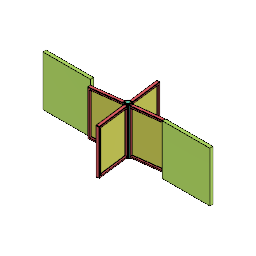
Revolving Door v0 (Autodesk Fusion 360 design; units mm, degrees)
Autodesk Fusion 360 part; units mm, degrees
sketch "Sketch1" plane through (0, 0, 0) normal (0, 0, 1) x (1, 0, 0) in component "base"
  line L0 (500, -10) -> (-500, -10)
  line L1 (-500, -10) -> (-500, 10)
  line L2 (-500, 10) -> (500, 10)
  line L3 (500, 10) -> (500, -10)
  line L4 (210, 10) -> (-210, 10)
  line L5 (-210, 10) -> (-210, -10)
  line L6 (-210, -10) -> (210, -10)
  line L7 (210, -10) -> (210, 10)
  line L8 (0, -10) -> (0, 10)
  line L9 (-215, 10) -> (-215, -10)
  line L10 (215, 10) -> (215, -10)
  dimension "d1" = 1000
  dimension "d2" = 20
  dimension "d3" = 420
  constraint horizontal L0
  constraint perpendicular L0 L1
  constraint parallel L0 L2
  constraint parallel L1 L3
  constraint horizontal L4
  constraint perpendicular L4 L5
  constraint parallel L4 L6
  constraint parallel L5 L7
  constraint midpoint L0 L8.start
  constraint midpoint L4 L8.end
  constraint perpendicular L4 L8
  constraint coincident L2 L9.start
  constraint coincident L0 L9.end
  constraint perpendicular L0 L9
  constraint coincident L2 L10.start
  constraint coincident L0 L10.end
  constraint perpendicular L0 L10
  measures "d1" distance of L1.end L2.end
  measures "d2" distance of L0.end L1.end
  measures "d3" distance of L5.end L6.end
sketch "Sketch1 (2)" plane through (0, 0, 0) normal (0, 1, 0) x (1, 0, 0) in component "glass door"
  line L0 (0, 0) -> (200, 0)
  line L1 (200, 0) -> (200, -270)
  line L2 (200, -270) -> (0, -270)
  line L3 (0, -270) -> (0, 0)
  line L4 (15, -15) -> (185, -15)
  line L5 (185, -15) -> (185, -255)
  line L6 (185, -255) -> (15, -255)
  line L7 (15, -255) -> (15, -15)
  dimension "d4" = 200
  dimension "d5" = 270
  dimension "d6" = 15
  constraint horizontal L0
  constraint vertical L1
  constraint horizontal L2
  constraint vertical L3
  constraint coincident L0.start L3.end
  measures "d4" distance of L0.start L0.end
  measures "d5" distance of L0.start L2.end
extrude "Extrude1" add sketch "Sketch1 (2)" along normal mid plane 20 makes body 1 in component "glass door"
move_body "Move1" bodies 1 to x (1, 0, 0) y (0, 1, 0) z (0, 0, 1) at (10, 0, 0) in component "glass door"
sketch "Sketch2" plane through (0, 0, 270) normal (0, 0, 1) x (-1, 0, 0) in component "glass door"
  line L0 (-210, 10) -> (-210, -10)
  line L1 (-210, -10) -> (-10, -10)
  line L2 (-10, -10) -> (-10, 10)
  line L3 (-10, 10) -> (-210, 10)
  line L4 (-10, 10) -> (-20, 10)
  line L5 (-20, 10) -> (-20, -10)
  line L6 (-10, -10) -> (-20, -10)
  line L7 (-10, -10) -> (-10, 10)
  line L8 (-15, -6.5) -> (-15, 6.5)
  line L9 (-15, -6.5) -> (-15, -5)
  line L10 (-20, -5) -> (-15, -5)
  line L11 (-20, 10) -> (-20, 5)
  line L12 (-15, 5) -> (-20, 5)
  line L13 (-20, -10) -> (-20, -7.5)
  line L14 (-14, -7.5) -> (-10, -7.5)
  line L15 (-10, 10) -> (-10, 7.5)
  line L16 (-10, 7.5) -> (-14, 7.5)
  arc A0 (-15, -6.5) -> (-14, -7.5) centre (-14, -6.5) ccw
  arc A1 (-14, 7.5) -> (-15, 6.5) centre (-14, 6.5) ccw
  dimension "d9" = 10
  dimension "d10" = 2.5
  dimension "d11" = 2.5
  dimension "d12" = 1
  dimension "d13" = 1
  constraint coincident L2.end L3.start
  constraint perpendicular L2 L4
  constraint coincident L1 L5.end
  constraint perpendicular L1 L5
  constraint coincident L1.end L2.start
  constraint perpendicular L1 L8
  constraint coincident L8 L9.end
  constraint perpendicular L1 L9
  constraint coincident L5 L10.start
  constraint perpendicular L8 L10
  constraint coincident L5 L11.end
  constraint perpendicular L3 L11
  constraint coincident L8 L12.start
  constraint perpendicular L8 L12
  constraint perpendicular L1 L13
  constraint coincident L2 L14.end
  constraint perpendicular L2 L14
  constraint perpendicular L4 L15
  constraint coincident L13.end L14
  constraint tangent L14 A0
  constraint tangent L9 A0
  constraint tangent L16 A1
  constraint tangent L8 A1
  measures "d9" distance of L2.end L4.end
  measures "d10" distance of L5.end L13.end
  measures "d11" distance of L2.end L15.end
  measures "d12" radius of A0
  measures "d13" radius of A1
extrude "Extrude2" cut sketch "Sketch2" against normal blind 300 contours L2 L3 L4 L5 L7 L8 L11 L12 L15 L16 A1 | L1 L2 L5 L6 L7 L8 L9 L10 L13 L14 A0 bodies 1 in component "glass door"
sketch "Sketch1 (3)" plane through (0, 0, 0) normal (0, 0, 1) x (1, 0, 0) in component "revolver base"
  circle A0 centre (0, 0) radius 10
  circle A1 centre (0, 0) radius 15
  dimension "d16" = 20
  dimension "d17" = 30
  constraint coincident A0.centre A1.centre
  measures "d16" diameter of A0
  measures "d17" diameter of A1
move_body "Move2" bodies 1 to x (1, 0, 0) y (0, 1, 0) z (0, 0, 1) at (0, 0, 5) in component "glass door"
extrude "Extrude1'" add sketch "Sketch1 (3)" along normal blind 5 separate body makes body 2 in component "revolver base"
sketch "Sketch1 (4)" plane through (0, 0, 5) normal (0, 0, 1) x (-1, 0, 0) in component "revolver"
  circle A0 centre (0, 0) radius 10
  circle A1 centre (0, 0) radius 15
  circle A2 centre (0, 0) radius 10
  line L0 (0, -10) -> (-20, -10)
  line L1 (-20, 10) -> (0, 10)
  line L2 (-10, -7.4988) -> (-14, -7.4988)
  line L3 (-15, -6.4988) -> (-15, 6.5)
  line L4 (-14, 7.5) -> (-10, 7.5)
  arc A3 (-15, -6.4988) -> (-14, -7.4988) centre (-14, -6.4988) ccw
  arc A4 (-14, 7.5) -> (-15, 6.5) centre (-14, 6.5) ccw
  line L5 (-15, -5) -> (-20, -5)
  line L6 (-15, 5) -> (-20, 5)
  line L7 (-20, -10) -> (-20, -5)
  line L8 (-20, 5) -> (-20, 10)
  line L9 (10, 0) -> (10, -20)
  line L10 (7.4988, -10) -> (7.4988, -14)
  arc A5 (6.4988, -15) -> (7.4988, -14) centre (6.4988, -14) ccw
  line L11 (6.4988, -15) -> (-6.5, -15)
  line L12 (5, -15) -> (5, -20)
  line L13 (10, -20) -> (5, -20)
  line L14 (-5, -15) -> (-5, -20)
  line L15 (-5, -20) -> (-10, -20)
  line L16 (-10, -20) -> (-10, 0)
  line L17 (-7.5, -14) -> (-7.5, -10)
  arc A6 (-7.5, -14) -> (-6.5, -15) centre (-6.5, -14) ccw
  line L18 (0, 10) -> (20, 10)
  line L19 (10, 7.4988) -> (14, 7.4988)
  arc A7 (15, 6.4988) -> (14, 7.4988) centre (14, 6.4988) ccw
  line L20 (15, 6.4988) -> (15, -6.5)
  line L21 (15, 5) -> (20, 5)
  line L22 (20, 10) -> (20, 5)
  line L23 (15, -5) -> (20, -5)
  line L24 (20, -5) -> (20, -10)
  line L25 (20, -10) -> (0, -10)
  line L26 (14, -7.5) -> (10, -7.5)
  arc A8 (14, -7.5) -> (15, -6.5) centre (14, -6.5) ccw
  line L27 (-10, 0) -> (-10, 20)
  line L28 (-7.4988, 10) -> (-7.4988, 14)
  arc A9 (-6.4988, 15) -> (-7.4988, 14) centre (-6.4988, 14) ccw
  line L29 (-6.4988, 15) -> (6.5, 15)
  line L30 (-5, 15) -> (-5, 20)
  line L31 (-10, 20) -> (-5, 20)
  line L32 (5, 15) -> (5, 20)
  line L33 (5, 20) -> (10, 20)
  line L34 (10, 20) -> (10, 0)
  line L35 (7.5, 14) -> (7.5, 10)
  arc A10 (7.5, 14) -> (6.5, 15) centre (6.5, 14) ccw
  dimension "d20" = 20
  dimension "d21" = 1
  dimension "d23" = 360
  constraint coincident A0.centre A1.centre
  constraint horizontal L0
  constraint vertical L7
  constraint horizontal L1
  constraint coincident A2 L0.start
  constraint parallel L0 L2
  constraint perpendicular L2 L3
  constraint perpendicular L3 L4
  constraint tangent L2 A3
  constraint tangent L3 A3
  constraint tangent L3 A4
  constraint tangent L4 A4
  constraint equal A3 A4
  constraint coincident L3 L5.start
  constraint perpendicular L3 L5
  constraint coincident L3 L6.start
  constraint coincident L6.end L7
  constraint perpendicular L6 L7
  constraint collinear L7 L8
  measures "d20" diameter of A2
  measures "d21" radius of A3
extrude "Extrude3" add sketch "Sketch1 (4)" along normal blind 275 separate body contours A0 A2 | A0 A2 L9 L25 | A0 A2 L18 L34 | A0 A2 L1 L27 | A0 A2 L0 L16 | A1 L9 L25 L26 | A1 L18 L19 L34 | A1 L1 L27 L28 | A1 L18 L34 L35 | A1 L0 L16 L17 | A1 L9 L10 L25 | A1 L20 L23 L24 L25 L26 A8 | A1 L18 L19 A7 L20 L21 L22 | A1 L0 L2 L16 | A1 L1 L4 L27 | A1 L27 L28 A9 L29 L30 L31 | A1 L29 L32 L33 L34 L35 A10 | A1 L11 L14 L15 L16 L17 A6 | A1 L9 L10 A5 L11 L12 L13 | A1 L0 L2 L3 A3 L5 L7 | A1 L1 L3 L4 A4 L6 L8 makes body 3 in component "revolver"
move_body "Move3" bodies 1 to x (1, 0, 0) y (0, 1, 0) z (0, 0, 1) at (150, 0, 0) in component "glass door"
copy_body "CopyPasteBodies1" bodies 1 makes body 4 in component "glass door"
move_body "Move4" bodies 4 to x (1, 0, 0) y (0, 1, 0) z (0, 0, 1) at (-250, 0, 0) in component "glass door"
move_body "Move5" bodies 4 to x (-1, 0, 0) y (0, -1, 0) z (0, 0, 1) at (50, 0, 0) in component "glass door"
copy_body "CopyPasteBodies2" bodies 4 makes body 5 in component "glass door"
move_body "Move6" bodies 5 to x (0, 1, 0) y (-1, 0, 0) z (0, 0, 1) at (150, -150, 0) in component "glass door"
copy_body "CopyPasteBodies3" bodies 5 makes body 6 in component "glass door"
move_body "Move7" bodies 6 to x (-1, 0, 0) y (0, -1, 0) z (0, 0, 1) at (300, 0, 0) in component "glass door"
extrude "Extrude4" add sketch "Sketch1 (4)" against normal blind 5 contours A0 A2 bodies 3 in component "revolver"
extrude "Extrude1''" add sketch "Sketch1" along normal blind 300 separate body contours L0 L2 L3 L10 | L0 L1 L2 L9 makes body 7 at (-310, -10, 100) makes body 8 at (405, -10, 100) in component "base"
sketch "Sketch2 (2)" plane through (0, 0, 280) normal (0, 0, 1) x (-1, 0, 0) in component "revolver"
  line L0 (-7.4988, 10) -> (-7.4988, 14)
  arc A0 (-6.4988, 15) -> (-7.4988, 14) centre (-6.4988, 14) ccw
  line L1 (-6.4988, 15) -> (-5, 15)
  line L2 (-5, 15) -> (-5, 20)
  line L3 (-5, 20) -> (-10, 20)
  line L4 (-10, 20) -> (-10, 10)
  line L5 (-10, 10) -> (-20, 10)
  line L6 (-20, 10) -> (-20, 5)
  line L7 (-20, 5) -> (-15, 5)
  line L8 (-15, 5) -> (-15, 6.5)
  arc A1 (-14, 7.5) -> (-15, 6.5) centre (-14, 6.5) ccw
  line L9 (-14, 7.5) -> (-10, 7.5)
  line L10 (-10, 7.5) -> (-10, -7.4988)
  line L11 (-10, -7.4988) -> (-14, -7.4988)
  arc A2 (-15, -6.4988) -> (-14, -7.4988) centre (-14, -6.4988) ccw
  line L12 (-15, -6.4988) -> (-15, -5)
  line L13 (-15, -5) -> (-20, -5)
  line L14 (-20, -5) -> (-20, -10)
  line L15 (-20, -10) -> (-10, -10)
  line L16 (-10, -10) -> (-10, -20)
  line L17 (-10, -20) -> (-5, -20)
  line L18 (-5, -20) -> (-5, -15)
  line L19 (-5, -15) -> (-6.5, -15)
  arc A3 (-7.5, -14) -> (-6.5, -15) centre (-6.5, -14) ccw
  line L20 (-7.5, -14) -> (-7.5, -10)
  line L21 (-7.5, -10) -> (7.4988, -10)
  line L22 (7.4988, -10) -> (7.4988, -14)
  arc A4 (6.4988, -15) -> (7.4988, -14) centre (6.4988, -14) ccw
  line L23 (6.4988, -15) -> (5, -15)
  line L24 (5, -15) -> (5, -20)
  line L25 (5, -20) -> (10, -20)
  line L26 (10, -20) -> (10, -10)
  line L27 (10, -10) -> (20, -10)
  line L28 (20, -10) -> (20, -5)
  line L29 (20, -5) -> (15, -5)
  line L30 (15, -5) -> (15, -6.5)
  arc A5 (14, -7.5) -> (15, -6.5) centre (14, -6.5) ccw
  line L31 (14, -7.5) -> (10, -7.5)
  line L32 (10, -7.5) -> (10, 7.4988)
  line L33 (10, 7.4988) -> (14, 7.4988)
  arc A6 (15, 6.4988) -> (14, 7.4988) centre (14, 6.4988) ccw
  line L34 (15, 6.4988) -> (15, 5)
  line L35 (15, 5) -> (20, 5)
  line L36 (20, 5) -> (20, 10)
  line L37 (20, 10) -> (10, 10)
  line L38 (10, 10) -> (10, 20)
  line L39 (10, 20) -> (5, 20)
  line L40 (5, 20) -> (5, 15)
  line L41 (5, 15) -> (6.5, 15)
  arc A7 (7.5, 14) -> (6.5, 15) centre (6.5, 14) ccw
  line L42 (7.5, 14) -> (7.5, 10)
  line L43 (7.5, 10) -> (-7.4988, 10)
  circle A8 centre (0, 0) radius 10
  dimension "d55" = 20
  constraint coincident A8.centre origin
  measures "d55" diameter of A8
extrude "Extrude5" add sketch "Sketch2 (2)" along normal blind 5 contours A8 bodies 3 in component "revolver"
sketch "Sketch2 (3)" plane through (0, 0, 280) normal (0, 0, 1) x (-1, 0, 0) in component "revolver base"
  arc A0 (-5.0004, 8.66) -> (-8.66, -5.0004) centre (0, 0) ccw
  line L0 (-5.0004, 8.66) -> (-11.4944, 4.9102)
  line L1 (-11.4944, 4.9102) -> (-13.4946, 8.3742)
  arc A1 (-13.1287, 9.7403) -> (-13.4946, 8.3742) centre (-12.6286, 8.8743) ccw
  line L2 (-13.1287, 9.7403) -> (-11.8307, 10.4898)
  line L3 (-11.8307, 10.4898) -> (-14.3309, 14.8198)
  line L4 (-14.3309, 14.8198) -> (-18.6609, 12.3196)
  line L5 (-18.6609, 12.3196) -> (-13.6604, 3.6596)
  line L6 (-13.6604, 3.6596) -> (-22.3204, -1.3409)
  line L7 (-22.3204, -1.3409) -> (-19.8202, -5.6709)
  line L8 (-19.8202, -5.6709) -> (-15.4902, -3.1707)
  line L9 (-15.4902, -3.1707) -> (-16.2403, -1.8717)
  arc A2 (-15.8743, -0.5056) -> (-16.2403, -1.8717) centre (-15.3743, -1.3716) ccw
  line L10 (-15.8743, -0.5056) -> (-12.4103, 1.4946)
  line L11 (-12.4103, 1.4946) -> (-8.66, -5.0004)
  circle A3 centre (0, 0) radius 15
  circle A4 centre (0, 0) radius 10
  dimension "d58" = 30
  dimension "d59" = 20
  constraint coincident A0.centre A3.centre
  measures "d58" diameter of A3
  measures "d59" diameter of A4
extrude "Extrude2'" add sketch "Sketch2 (3)" along normal blind 5 separate body contours A0 L0 L1 L5 L6 L10 L11 A3 A4 | L0 L1 L10 L11 A3 A4 | L5 L6 A3 makes body 9 in component "revolver base"
sketch "Sketch2 (4)" plane through (-168.8705, -97.509, 0) normal (0.866, 0.500044, 0) x (-0.500044, 0.866, 0)
  line L0 (10, 262.5) -> (-10, 262.5)
  line L1 (-10, 262.5) -> (-10, 22.5)
  line L2 (-10, 22.5) -> (10, 22.5)
  line L3 (10, 22.5) -> (10, 262.5)
sketch "Sketch3" plane through (-168.8705, -97.509, 142.5) normal (0.866, 0.500044, 0) x (-0.500044, 0.866, 0)
  line L0 (2.5, -129.1153) -> (-2.5, -129.1153)
  line L1 (-2.5, -129.1153) -> (-2.5, 129.1153)
  line L2 (-2.5, 129.1153) -> (2.5, 129.1153)
  line L3 (2.5, 129.1153) -> (2.5, -129.1153)
  line L4 (2.5, -129.1153) -> (-2.5, 129.1153) construction
  line L5 (-2.5, -129.1153) -> (2.5, 129.1153) construction
  dimension "d62" = 5
  constraint horizontal L0
  constraint perpendicular L0 L1
  constraint parallel L0 L2
  constraint parallel L1 L3
  constraint coincident L4 origin
  constraint coincident L5 origin
  measures "d62" distance of L1.end L2.end
sketch "Sketch3 (2)" plane through (345, 0, 0) normal (-1, 0, 0) x (0, -1, 0) in component "glass door"
  line L0 (10, 260) -> (-10, 260)
  line L1 (-10, 260) -> (-10, 20)
  line L2 (-10, 20) -> (10, 20)
  line L3 (10, 20) -> (10, 260)
  line L4 (2.5, 10) -> (-2.5, 10)
  line L5 (-2.5, 10) -> (-2.5, 270)
  line L6 (-2.5, 270) -> (2.5, 270)
  line L7 (2.5, 270) -> (2.5, 10)
  line L8 (2.5, 10) -> (-2.5, 270) construction
  line L9 (-2.5, 10) -> (2.5, 270) construction
  point P0 (0, 140)
  dimension "d63" = 5
  dimension "d64" = 260
  constraint horizontal L4
  constraint perpendicular L4 L5
  constraint parallel L4 L6
  constraint parallel L5 L7
  constraint coincident L8 P0
  constraint coincident L9 P0
  measures "d63" distance of L5.end L6.end
  measures "d64" distance of L4.end L5.end
extrude "Extrude3'" cut sketch "Sketch3 (2)" along normal blind 180 and the other way blind 10 contours L0 L2 L5 L7 bodies 1 in component "glass door"
extrude "Extrude4'" cut sketch "Sketch3 (2)" along normal blind 180 and the other way blind 10 from surface at 220 contours L0 L2 L5 L7 bodies 4 in component "glass door"
sketch "Sketch4" plane through (0, -195, 0) normal (0, 1, 0) x (-1, 0, 0) in component "glass door"
  line L0 (-140, 260) -> (-160, 260)
  line L1 (-160, 260) -> (-160, 20)
  line L2 (-160, 20) -> (-140, 20)
  line L3 (-140, 20) -> (-140, 260)
  line L4 (-147.5, 270) -> (-152.5, 270)
  line L5 (-152.5, 270) -> (-152.5, 10)
  line L6 (-152.5, 10) -> (-147.5, 10)
  line L7 (-147.5, 10) -> (-147.5, 270)
  line L8 (-147.5, 270) -> (-152.5, 10) construction
  line L9 (-152.5, 270) -> (-147.5, 10) construction
  point P0 (-150, 140)
  dimension "d74" = 5
  dimension "d75" = 260
  constraint horizontal L4
  constraint perpendicular L4 L5
  constraint parallel L4 L6
  constraint parallel L5 L7
  constraint coincident L8 P0
  constraint coincident L9 P0
  measures "d74" distance of L5.end L6.end
  measures "d75" distance of L4.end L5.end
extrude "Extrude5'" cut sketch "Sketch4" along normal blind 180 and the other way blind 10 contours L0 L2 L5 L7 bodies 5 in component "glass door"
extrude "Extrude6" cut sketch "Sketch4" along normal blind 10 and the other way blind 180 from surface at 390 contours L0 L2 L5 L7 bodies 6 in component "glass door"
extrude "Extrude1'''" add 1 faces at (150.8333, 205, 180) along direction (0, -1, 0) blind 190 separate body on bodies 6 makes body 10 in component "Component"
extrude "Extrude2''" add 1 faces at (-55, 0.8333, 180) along direction (1, 0, 0) blind 190 separate body on bodies 4 makes body 11 in component "Component"
extrude "Extrude3''" add 1 faces at (150.8333, -205, 180) along direction (0, 1, 0) blind 190 separate body on bodies 5 makes body 12 in component "Component"
extrude "Extrude4''" add 1 faces at (355, 0.8333, 180) along direction (-1, 0, 0) blind 190 separate body on bodies 1 makes body 13 in component "Component"
fillet "Fillet1" radius 2 32 edges at (265, 10, 275) (265, -10, 275) (360, 10, 140) (360, -10, 140) (265, 10, 5) (360, 0, 5) (265, -10, 5) (360, 0, 275) (35, 10, 275) (35, -10, 275) (-60, -10, 140) (-60, 10, 140) (-60, 0, 275) (-60, 0, 5) (35, -10, 5) (35, 10, 5) (140, -115, 275) (160, -115, 275) (140, -210, 140) (160, -210, 140) (160, -115, 5) (150, -210, 275) (150, -210, 5) (140, -115, 5) (140, 115, 275) (160, 115, 275) (150, 210, 275) (140, 210, 140) (160, 210, 140) (160, 115, 5) (150, 210, 5) (140, 115, 5) on bodies 1 4 5 6 in component "glass door"
fillet "Fillet2" radius 5 32 edges at (345, 10, 140) (260, 10, 260) (260, 10, 20) (175, 10, 140) (260, -10, 20) (175, -10, 140) (260, -10, 260) (345, -10, 140) (40, 10, 260) (125, 10, 140) (40, 10, 20) (-45, 10, 140) (40, -10, 20) (125, -10, 140) (40, -10, 260) (-45, -10, 140) (140, -110, 260) (140, -195, 140) (160, -195, 140) (160, -110, 260) (160, -110, 20) (160, -25, 140) (140, -110, 20) (140, -25, 140) (140, 110, 20) (140, 110, 260) (140, 195, 140) (140, 25, 140) (160, 110, 20) (160, 25, 140) (160, 110, 260) (160, 195, 140) on bodies 1 4 5 6 in component "glass door"
component "base" placed x (1, 0, 0) y (0, 1, 0) z (0, 0, 1) at (0, 0, 0)
component "glass door" placed x (-0.866, -0.500044, 0) y (0.500044, -0.866, 0) z (0, 0, 1) at (129.8995, 75.0064, 2.5)
component "revolver base" placed x (1, 0, 0) y (0, 1, 0) z (0, 0, 1) at (0, 0, 0)
component "revolver" placed x (-0.866, -0.500044, 0) y (0.500044, -0.866, 0) z (0, 0, 1) at (0, 0, 0)
component "Component" placed x (1, 0, 0) y (0, 1, 0) z (0, 0, 1) at (0, 0, 0) in component "glass door"
